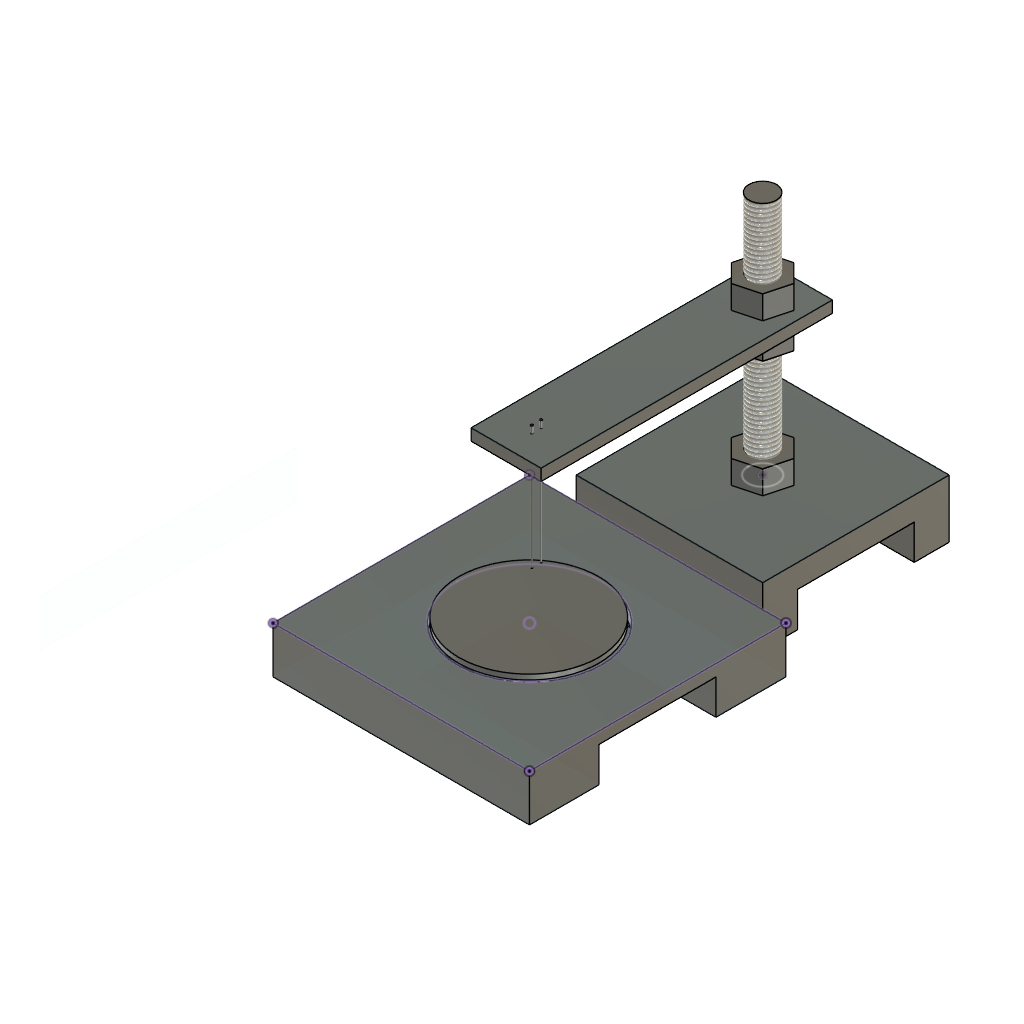
Modelo Plasma V2 (Autodesk Fusion 360 design; units mm, degrees)
part number: 2026-10-17-21-30-55-708
Autodesk Fusion 360 part; units mm, degrees
sketch "Boceto1" plane through (0, 0, 0) normal (0, 0, 1) x (1, 0, 0)
  line L0 (0, 0) -> (2.5, 0)
  line L1 (2.5, 0) -> (2.5, 2.5)
  line L2 (2.5, 2.5) -> (0, 2.5)
  line L3 (0, 2.5) -> (0, 0)
  constraint horizontal L0
  constraint vertical L1
  constraint horizontal L2
  constraint vertical L3
  constraint coincident L0.start L3.end
extrude "Extruir1" add sketch "Boceto1" along normal blind 1.5 makes body 1
delete_face "SuperficieEliminarCara1" leaving the opening 3 faces at (0.8333, 1.6667, 1.5) (0, 1.6667, 0.5) (1.6667, 2.5, 0.5) on bodies 1
delete_face "SuperficieEliminarCara2" leaving the opening 1 faces at (0.8333, 1.6667, 0) on bodies 1
delete_face "SuperficieEliminarCara3" leaving the opening 1 faces at (2.5, 0.8333, 0.5) on bodies 1
delete_face "SuperficieEliminarCara4" leaving the opening 1 faces at (0.8333, 0, 0.5) on bodies 1
sketch "Boceto2" plane through (0, 0, 0) normal (0, 0, 1) x (1, 0, 0)
sketch "Boceto3" plane through (0, 0, 0) normal (0, 0, 1) x (1, 0, 0)
  line L0 (-40, 40) -> (40, 40)
  line L1 (40, 40) -> (40, -40)
  line L2 (40, -40) -> (-40, -40)
  line L3 (-40, -40) -> (-40, 40)
  line L4 (-40, 40) -> (40, -40) construction
  line L5 (40, 40) -> (-40, -40) construction
  dimension "d3" = 80
  dimension "d4" = 80
  constraint horizontal L0
  constraint perpendicular L0 L1
  constraint parallel L0 L2
  constraint parallel L1 L3
  constraint coincident L4 origin
  constraint coincident L5 origin
  measures "d3" distance of L1.end L2.end
  measures "d4" distance of L0.end L1.end
extrude "Extruir2" add sketch "Boceto3" along normal blind 25 separate body makes body 2
sketch "Boceto4" plane through (0, 0, 25) normal (0, 0, 1) x (-1, 0, 0)
  line L0 (40, 40) -> (-40, 40)
  line L1 (-40, 40) -> (-40, -40)
  line L2 (-40, -40) -> (40, -40)
  line L3 (40, -40) -> (40, 40)
  circle A0 centre (0, 0) radius 6.25
  dimension "d7" = 12.5
  constraint coincident A0.centre origin
  measures "d7" diameter of A0
extrude "Extruir3" cut sketch "Boceto4" against normal blind 15 contours A0 bodies 2
sketch "Boceto5" plane through (0, 0, 25) normal (0, 0, 1) x (-1, 0, 0)
  circle A0 centre (0, 0) radius 6.25
  line L0 (40, 40) -> (-40, 40)
  line L1 (-40, 40) -> (-40, -40)
  line L2 (-40, -40) -> (40, -40)
  line L3 (40, -40) -> (40, 40)
  line L4 (15.0594, -15) -> (-14.9406, -15)
  line L5 (-14.9406, -15) -> (-14.9406, 110)
  line L6 (-14.9406, 110) -> (15.0594, 110)
  line L7 (15.0594, 110) -> (15.0594, -15)
  circle A1 centre (0, 0) radius 3.1
  circle A2 centre (0, 95) radius 0.4
  circle A3 centre (0, 99) radius 0.4
  point P0 (0, 99)
  dimension "d10" = 30
  dimension "d11" = 125
  dimension "d12" = 0.8
  dimension "d59" = 0.8
  constraint horizontal L4
  constraint vertical L5
  constraint horizontal L6
  constraint vertical L7
  constraint coincident A0.centre A1.centre
  constraint coincident P0 A3.centre
  measures "d10" distance of L4.start L4.end
  measures "d11" distance of L4.start L6.end
  measures "d12" diameter of A2
  measures "d59" diameter of A3
extrude "Extruir4" add sketch "Boceto5" along normal blind 5 separate body contours L0 L4 L5 L7 | L0 L5 L6 L7 makes body 3
cylinder "CilindroPrimitivo1" add diameter 12 height 130 placed x (1, 0, 0) y (0, 1, 0) z (0, 0, 1) at (0, 0, 0) separate body makes body 4
move_body "Desplazar1" bodies 3 to x (1, 0, 0) y (0, 1, 0) z (0, 0, 1) at (0, 0, 40)
sketch "Boceto7" plane through (0, 0, 0) normal (0, 0, 1) x (1, 0, 0)
  circle A0 centre (0, -95) radius 30
  dimension "d18" = 60
  measures "d18" diameter of A0
extrude "Extruir5" add sketch "Boceto7" along normal blind 15 separate body makes body 5
sketch "Boceto8" plane through (0, 0, 15) normal (0, 0, 1) x (-1, 0, 0)
  circle A0 centre (0, 95) radius 30
  circle A1 centre (0, 95) radius 42.5
  dimension "d21" = 85
  constraint concentric A0 A1
  measures "d21" diameter of A1
extrude "Extruir6" cut sketch "Boceto8" against normal blind 12.8 contours A0 | A1 bodies 5
sketch "Boceto9" plane through (0, 0, 130) normal (0, 0, 1) x (-1, 0, 0)
  circle A0 centre (0, 0) radius 6
  line L0 (55, 255) -> (-55, 255)
  line L1 (-55, 255) -> (-55, 145)
  line L2 (-55, 145) -> (55, 145)
  line L3 (55, 145) -> (55, 255)
  line L4 (55, 255) -> (-55, 145) construction
  line L5 (-55, 255) -> (55, 145) construction
  point P0 (0, 200)
  dimension "d24" = 110
  dimension "d25" = 110
  constraint horizontal L0
  constraint perpendicular L0 L1
  constraint parallel L0 L2
  constraint parallel L1 L3
  constraint coincident L4 P0
  constraint coincident L5 P0
  measures "d24" distance of L1.end L2.end
  measures "d25" distance of L0.end L1.end
extrude "Extruir7" add sketch "Boceto9" along normal blind 20 separate body contours L0 L1 L2 L3 makes body 6
move_body "Desplazar2" bodies 6 to x (1, 0, 0) y (0, 1, 0) z (0, 0, 1) at (0, 0, -70)
sketch "Boceto10" plane through (0, 0, 80) normal (0, 0, 1) x (-1, 0, 0)
  line L0 (55, 145) -> (55, 255)
  line L1 (55, 255) -> (-55, 255)
  line L2 (-55, 255) -> (-55, 145)
  line L3 (-55, 145) -> (55, 145)
  circle A0 centre (0, 200) radius 31
  dimension "d28" = 62
  measures "d28" diameter of A0
extrude "Extruir8" cut sketch "Boceto10" against normal blind 5 contours A0 bodies 6
sketch "Boceto11" plane through (-55, 0, 0) normal (-1, 0, 0) x (0, -1, 0)
  line L0 (145, 60) -> (255, 60)
  line L1 (255, 60) -> (255, 80)
  line L2 (255, 80) -> (145, 80)
  line L3 (145, 80) -> (145, 60)
sketch "Boceto12" plane through (55, 0, 0) normal (1, 0, 0) x (0, 1, 0)
  line L0 (-255, 60) -> (-145, 60)
  line L1 (-145, 60) -> (-145, 80)
  line L2 (-145, 80) -> (-255, 80)
  line L3 (-255, 80) -> (-255, 60)
  line L4 (-225.159, 75) -> (-175.0625, 75)
  line L5 (-175.0625, 75) -> (-175.0625, 60)
  line L6 (-175.0625, 60) -> (-225.159, 60)
  line L7 (-225.159, 60) -> (-225.159, 75)
  constraint horizontal L4
  constraint vertical L5
  constraint horizontal L6
  constraint vertical L7
  constraint coincident L0 L5.end
extrude "Extruir9" cut sketch "Boceto12" against normal blind 80 contours L0 L4 L5 L6 L7 bodies 6
move_body "Desplazar3" bodies 5 to x (1, 0, 0) y (0, 1, 0) z (0, 0, 1) at (0, -105, 25)
move_body "Desplazar4" bodies 5 6 to x (1, 0, 0) y (0, 1, 0) z (0, 0, 1) at (0, 100, 0)
move_body "Desplazar5" bodies 5 6 to x (1, 0, 0) y (0, 1, 0) z (0, 0, 1) at (0, -65, 0)
move_body "Desplazar6" bodies 5 to x (1, 0, 0) y (0, 1, 0) z (0, 0, 1) at (0, 70, 0)
move_body "Desplazar7" bodies 6 to x (1, 0, 0) y (0, 1, 0) z (0, 0, 1) at (0, -45, 0)
thread "Rosca1" "ISO Metric profile 12.0 M12x1.75 M12x1.75 6g" major diameter 11.8335 minor diameter 9.8365 pitch 1.75 angle 60 resizes the face on face at (5.9702, -0.5974, 86.6667) on bodies 4
sketch "Boceto13" plane through (0, 0, 70) normal (0, 0, 1) x (-1, 0, 0)
  circle A0 centre (0, 0) radius 6.25
  circle A1 centre (0, 95) radius 0.4
  line L0 (15.0594, 110) -> (-14.9406, 110)
  line L1 (-14.9406, 110) -> (-14.9406, -15)
  line L2 (-14.9406, -15) -> (15.0594, -15)
  line L3 (15.0594, -15) -> (15.0594, 110)
  line L4 (2.8392, 10.5959) -> (-7.7567, 7.7567)
  line L5 (-7.7567, 7.7567) -> (-10.5959, -2.8392)
  line L6 (-10.5959, -2.8392) -> (-2.8392, -10.5959)
  line L7 (-2.8392, -10.5959) -> (7.7567, -7.7567)
  line L8 (7.7567, -7.7567) -> (10.5959, 2.8392)
  line L9 (10.5959, 2.8392) -> (2.8392, 10.5959)
  circle A2 centre (0, 0) radius 6
  circle A3 centre (0, 99) radius 0.4
  dimension "d35" = 9.5
  dimension "d36" = 12
  constraint coincident A0.centre A2.centre
  measures "d35" distance of A0.centre L9
  measures "d36" diameter of A2
extrude "Extruir10" add sketch "Boceto13" along normal blind 10 separate body contours L4 L5 L6 L7 L8 L9 makes body 7
thread "Rosca2" "ISO Metric profile 12.0 M12x1.75 M12x1.75 6H" major diameter 12.2265 minor diameter 10.2735 pitch 1.75 angle 60 modelled right hand crest width 0.4769 on face at (-6.2422, 0.3115, 76.6667) crest through (-5.1368, 0, 70.4375) on bodies 7
copy_body "CopiarPegarCuerpos1" bodies 7 makes body 8
move_body "Desplazar8" bodies 8 to x (1, 0, 0) y (0, 1, 0) z (0, 0, 1) at (0, 0, -10)
move_body "Desplazar9" bodies 8 to x (1, 0, 0) y (0, 1, 0) z (0, 0, 1) at (0, 0, -5)
cylinder "CilindroPrimitivo2" add diameter 0.6 height 47 placed x (1, 0, 0) y (0, 1, 0) z (0, 0, 1) at (0, -95, 70) separate body makes body 9
cylinder "CilindroPrimitivo3" add diameter 1 height 6 placed x (1, 0, 0) y (0, 1, 0) z (0, 0, 1) at (0, -95, 117) bodies 9
move_body "Desplazar10" bodies 6 to x (1, 0, 0) y (0, 1, 0) z (0, 0, 1) at (0, 110, -30)
move_body "Desplazar11" bodies 5 to x (1, 0, 0) y (0, 1, 0) z (0, 0, 1) at (-0.2039, -5.1269, 0)
move_body "Desplazar12" bodies 6 to x (1, 0, 0) y (0, 1, 0) z (0, 0, 1) at (0, 0, -30)
move_body "Desplazar13" bodies 5 to x (1, 0, 0) y (0, 1, 0) z (0, 0, 1) at (0, 0, 10)
sketch "Boceto20" plane through (0, 0, 0) normal (0, 0, 1) x (1, 0, 0)
  line L0 (137.5, -62.5) -> (62.5, -62.5)
  line L1 (62.5, -62.5) -> (62.5, -137.5)
  line L2 (62.5, -137.5) -> (137.5, -137.5)
  line L3 (137.5, -137.5) -> (137.5, -62.5)
  line L4 (137.5, -62.5) -> (62.5, -137.5) construction
  line L5 (62.5, -62.5) -> (137.5, -137.5) construction
  point P0 (100, -100)
  dimension "d47" = 75
  dimension "d48" = 75
  constraint horizontal L0
  constraint perpendicular L0 L1
  constraint parallel L0 L2
  constraint parallel L1 L3
  constraint coincident L4 P0
  constraint coincident L5 P0
  measures "d47" distance of L1.end L2.end
  measures "d48" distance of L0.end L1.end
extrude "Extruir11" add sketch "Boceto20" along normal blind 0.5 bodies 6 makes body 10
move_body "Desplazar14" bodies 10 to x (1, 0, 0) y (0, 1, 0) z (0, 0, 1) at (-100, 0, 30)
move_body "Desplazar15" bodies 9 to x (1, 0, 0) y (0, 1, 0) z (0, 0, 1) at (0, 0, -30)
move_body "Desplazar16" bodies 3 to x (1, 0, 0) y (0, 1, 0) z (0, 0, 1) at (0, 0, 20)
move_body "Desplazar17" bodies 7 to x (1, 0, 0) y (0, 1, 0) z (0, 0, 1) at (0, 0, 20)
move_body "Desplazar18" bodies 8 to x (1, 0, 0) y (0, 1, 0) z (0, 0, 1) at (0, 0, 20)
move_body "Desplazar19" bodies 10 to x (1, 0, 0) y (0, 1, 0) z (0, 0, 1) at (0, 0, -10)
move_body "Desplazar20" bodies 5 to x (1, 0, 0) y (0, 1, 0) z (0, 0, 1) at (0, 0, -10)
move_body "Desplazar21" bodies 5 to x (1, 0, 0) y (0, 1, 0) z (0, 0, 1) at (0, 0, -5)
move_body "Desplazar22" bodies 10 to x (1, 0, 0) y (0, 1, 0) z (0, 0, 1) at (0, 0, -10)
sketch "Boceto21" plane through (0, 0, 0) normal (0, 0, 1) x (1, 0, 0)
  line L0 (40, 25) -> (-40, 25)
  line L1 (-40, 25) -> (-40, -25)
  line L2 (-40, -25) -> (40, -25)
  line L3 (40, -25) -> (40, 25)
  constraint horizontal L0
  constraint vertical L1
  constraint horizontal L2
  constraint vertical L3
move_body "Desplazar23" bodies 4 to x (1, 0, 0) y (0, 1, 0) z (0, 0, 1) at (0, 0, 30)
extrude "Extruir12" cut sketch "Boceto21" along normal blind 15 bodies 2
move_body "Desplazar24" bodies 4 to x (1, 0, 0) y (0, 1, 0) z (0, 0, 1) at (0, 0, -30)
copy_body "CopiarPegarCuerpos2" bodies 8 makes body 11
move_body "Desplazar25" bodies 11 to x (1, 0, 0) y (0, 1, 0) z (0, 0, 1) at (0, 0, -50)
copy_body "CopiarPegarCuerpos3" bodies 11 makes body 12
move_body "Desplazar26" bodies 12 to x (1, 0, 0) y (0, 1, 0) z (0, 0, 1) at (0, 0, -20)
copy_body "CopiarPegarCuerpos4" bodies 9 makes body 13
move_body "Desplazar27" bodies 13 to x (1, 0, 0) y (0, 1, 0) z (0, 0, 1) at (0, -4, 0)
move_body "Desplazar28" bodies 5 to x (1, 0, 0) y (0, 1, 0) z (0, 0, 1) at (0, -110, 0)
move_body "Desplazar29" bodies 10 to x (1, 0, 0) y (0, 1, 0) z (0, 0, 1) at (0, -110, 0)
sketch "Boceto22" plane through (0, 0, 90) normal (0, 0, 1) x (-1, 0, 0)
  circle A0 centre (0, 0) radius 6.25
  circle A1 centre (0, 95) radius 0.4
  circle A2 centre (0, 99) radius 0.4
  line L0 (15.0594, 110) -> (-14.9406, 110)
  line L1 (-14.9406, 110) -> (-14.9406, -15)
  line L2 (-14.9406, -15) -> (15.0594, -15)
  line L3 (15.0594, -15) -> (15.0594, 110)
sketch "Boceto23" plane through (0, 0, 20) normal (0, 0, 1) x (-1, 0, 0)
  circle A0 centre (0, 100) radius 31
  line L0 (55, 45) -> (55, 155)
  line L1 (55, 155) -> (-55, 155)
  line L2 (-55, 155) -> (-55, 45)
  line L3 (-55, 45) -> (55, 45)
sketch "Boceto24" plane through (0, 0, 0) normal (0, 0, -1) x (1, 0, 0)
  line L0 (-25, 125.159) -> (55, 125.159)
  line L1 (55, 125.159) -> (55, 155)
  line L2 (55, 155) -> (-55, 155)
  line L3 (-55, 155) -> (-55, 45)
  line L4 (-55, 45) -> (55, 45)
  line L5 (55, 45) -> (55, 75.0625)
  line L6 (55, 75.0625) -> (-25, 75.0625)
  line L7 (-25, 75.0625) -> (-25, 125.159)
move_body "Desplazar30" bodies 5 to x (1, 0, 0) y (0, 1, 0) z (0, 0, 1) at (0, 110, 0)
move_body "Desplazar31" bodies 10 to x (1, 0, 0) y (0, 1, 0) z (0, 0, 1) at (0, 110, 0)
named bodies: "base torre", "Puente electrodo +", "Tornillo columna", "Petri", "Base_petri", "Tuerca", "Tuerca (1)", "Aguja Electrodo", "Placa de Cobre", "Tuerca (1) (1)", "Tuerca (1) (1) (1)", "Aguja Electrodo (1)"
